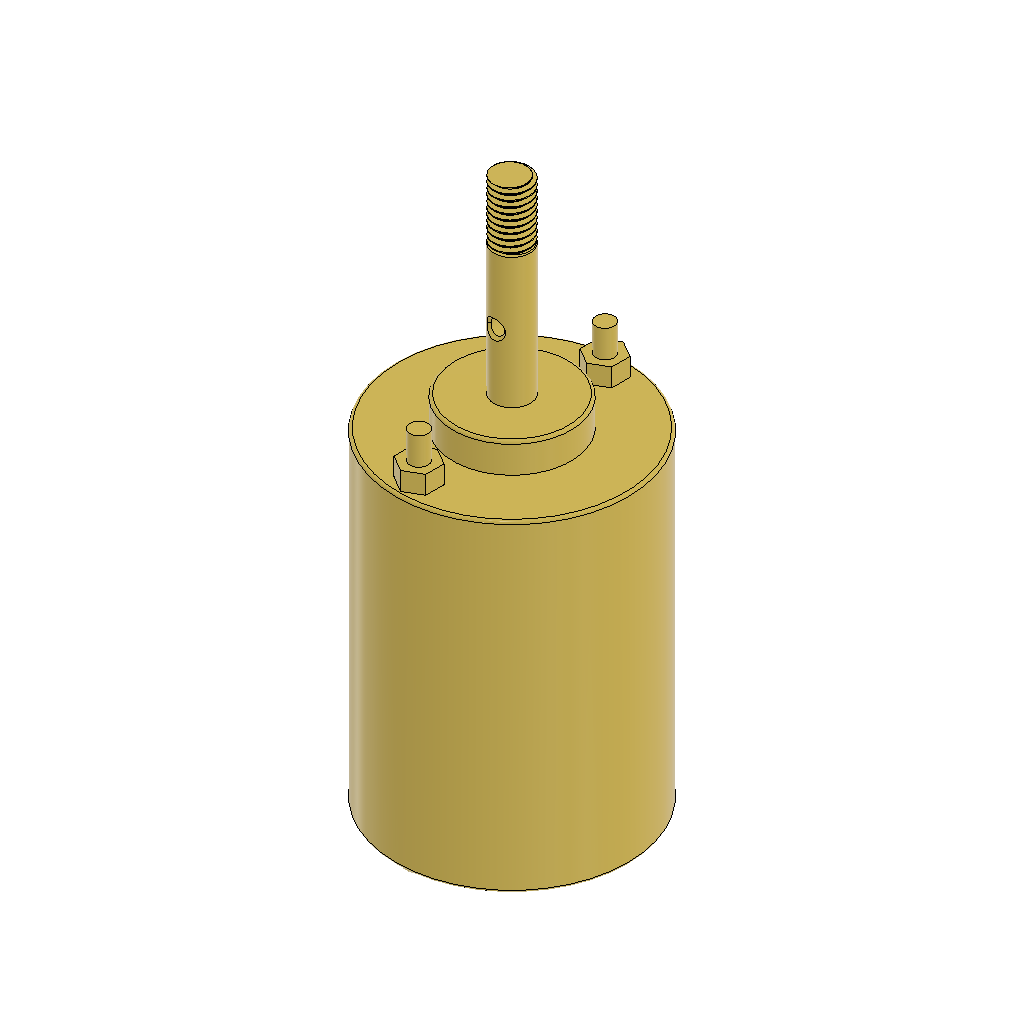
3420 Motor 12-24V 30W A3 (Autodesk Fusion 360 design; units mm, degrees)
Autodesk Fusion 360 part; units mm, degrees
sketch "Sketch1" plane through (0, 0, 0) normal (0, 0, 1) x (1, 0, 0)
  circle A0 centre (0, 0) radius 25.5
  circle A1 centre (0, 0) radius 13
  circle A2 centre (0, 0) radius 4
  circle A3 centre (0, 20.5) radius 2
  circle A4 centre (0, -20.5) radius 2
  circle A5 centre (0, 20.5) radius 3.25
  circle A6 centre (0, -20.5) radius 3.25
  line L0 (6.7341, 3.8879) -> (0, 7.7759)
  line L1 (0, 7.7759) -> (-6.7341, 3.8879)
  line L2 (-6.7341, 3.8879) -> (-6.7341, -3.8879)
  line L3 (-6.7341, -3.8879) -> (0, -7.7759)
  line L4 (0, -7.7759) -> (6.7341, -3.8879)
  line L5 (6.7341, -3.8879) -> (6.7341, 3.8879)
  circle A7 centre (-10.1748, 14.8287) radius 4.5
  circle A8 centre (-10.1748, 16.3287) radius 1.5
  circle A9 centre (-10.1748, 13.3287) radius 1.5
  circle A10 centre (0, 0) radius 5.5
  line L6 (3.5, 22.5207) -> (0, 24.5415)
  line L7 (0, 24.5415) -> (-3.5, 22.5207)
  line L8 (-3.5, 22.5207) -> (-3.5, 18.4793)
  line L9 (-3.5, 18.4793) -> (0, 16.4585)
  line L10 (0, 16.4585) -> (3.5, 18.4793)
  line L11 (3.5, 18.4793) -> (3.5, 22.5207)
  line L12 (3.5, -18.4793) -> (0, -16.4585)
  line L13 (0, -16.4585) -> (-3.5, -18.4793)
  line L14 (-3.5, -18.4793) -> (-3.5, -22.5207)
  line L15 (-3.5, -22.5207) -> (0, -24.5415)
  line L16 (0, -24.5415) -> (3.5, -22.5207)
  line L17 (3.5, -22.5207) -> (3.5, -18.4793)
  point P0 (0, 20.5)
  point P1 (0, -20.5)
  dimension "d1" = 51
  dimension "d2" = 26
  dimension "d3" = 8
  dimension "d4" = 4
  dimension "d6" = 20.5
  dimension "d7" = 20.5
  dimension "d8" = 6.5
  dimension "d10" = 15.5517
  dimension "d11" = 9
  dimension "d12" = 3
  dimension "d15" = 11
  dimension "d41" = 3.5
  dimension "d42" = 3.5
  constraint coincident A0.centre A1.centre
  constraint vertical A0.centre A3.centre
  constraint vertical A0.centre P1
  constraint concentric A3 A5
  constraint concentric A4 A6
  constraint equal A5 A6
  constraint equal A3 A4
  constraint vertical L5
  constraint equal A8 A9
  constraint vertical A7.centre A8.centre
  constraint vertical A7.centre A9.centre
  constraint concentric A2 A10
  constraint coincident A7.centre A8
  constraint tangent A8 A9
  constraint coincident P0 A3.centre
  constraint vertical L11
  constraint coincident P1 A4.centre
  constraint vertical L17
  measures "d1" diameter of A0
  measures "d2" diameter of A1
  measures "d3" diameter of A2
  measures "d4" diameter of A3
  measures "d6" distance of A0.centre P0
  measures "d7" distance of A0.centre P1
  measures "d8" diameter of A5
  measures "d10" distance of L0.end L3.end
  measures "d11" diameter of A7
  measures "d12" diameter of A8
  measures "d15" diameter of A10
  measures "d41" distance of P0 L11
  measures "d42" distance of P1 L17
extrude "Extrude1" add sketch "Sketch1" against normal blind 6.5 contours A1 | A2 | L0 L1 L2 L3 L4 L5 | A10 makes body 1
extrude "Extrude2" add sketch "Sketch1" against normal blind 71 from surface at -6.5 contours A0 | A1 | A2 | A3 | A4 | A5 | A6 | L0 L1 L2 L3 L4 L5 | A7 | A8 | A9 | A10 | L6 L7 L8 L9 L10 L11 | L12 L13 L14 L15 L16 L17 bodies 1
extrude "Extrude3" add sketch "Sketch1" against normal blind 6.5 from surface at -77.5 contours A1 | A2 | L0 L1 L2 L3 L4 L5 | A10 bodies 1
extrude "Extrude4" cut sketch "Sketch1" along normal blind 2 from surface at -84 contours A10 bodies 1
extrude "Extrude5" add sketch "Sketch1" against normal blind 2.5 from surface at -77.5 contours A3 | A4 | A5 | A6 bodies 1
extrude "Extrude6" add sketch "Sketch1" against normal blind 3 from surface at -77.5 contours A7 bodies 1
extrude "Extrude7" add sketch "Sketch1" against normal blind 10 from surface at -77.5 contours A8 | A9 bodies 1
extrude "Extrude8" add sketch "Sketch1" along normal blind 28.7069 contours A2 bodies 1
extrude "Extrude12" add 1 faces at (-1.2456, 0.0132, 28.7069) along direction (0, 0, 1) blind 13 separate body on bodies 1 makes body 2
extrude "Extrude9" add sketch "Sketch1" along normal blind 10 from surface at -6.5 separate body contours A3 | A4 makes body 3 at (1.9975, 20.4003, 0.1667) makes body 4 at (1.9975, -20.5997, 0.1667)
extrude "Extrude10" add sketch "Sketch1" along normal blind 4 from surface at -6.5 contours A5 | A6 | L6 L7 L8 L9 L10 L11 | L12 L13 L14 L15 L16 L17 bodies 1 3 4
sketch "Sketch2" plane through (0, 0, 0) normal (0, 1, 0) x (1, 0, 0)
  circle A0 centre (0, -14.2069) radius 1.5
  line L0 (-4, -41.7069) -> (4, -41.7069)
  dimension "d46" = 3
  dimension "d54" = 27.5
  constraint vertical origin A0.centre
  measures "d46" diameter of A0
  measures "d54" distance of A0.centre L0
extrude "Extrude11" cut sketch "Sketch2" along normal mid plane 20 bodies 1
thread "Thread1" "ISO Metric profile 8.0 M8x1.25 M8x1.25 6g" major diameter 7.866 minor diameter 6.4455 pitch 1.25 angle 60 modelled right hand crest width 0.1833 on face at (3.9801, -0.3983, 33.0402) crest through (3.933, 0, 28.3944) on bodies 2
fillet "Fillet1" radius 0.6 4 edges at (-12.1203, -4.701, 0) (-12.1203, 4.701, -84) (-23.7743, -9.2212, -6.5) (-23.7743, 9.2212, -77.5) on bodies 1
fillet "Fillet2" radius 1.6 2 edges at (-3.0301, 21.6753, -80) (-3.0301, -19.3247, -80) on bodies 1
chamfer "Chamfer1" distance 0.6 angle 45 2 edges at (1.5, 3.7081, 14.2069) (1.5, -3.7081, 14.2069) tangent chain off on bodies 1
combine "Combine1" operation add target body 1 tool bodies 2
equation "d6 = ( 41 / 2 ) * 1 mm"
equation "d7 = ( 41 / 2 ) * 1 mm"
equation "d10 = ( 44 * 41 / 116 ) * 1 mm"
equation "d13 = d12 / 2 + 0.5 mm"
equation "d36 = ( 118 * 41 / 116 ) * 1 mm - 13 mm"
equation "d42 = d41"
